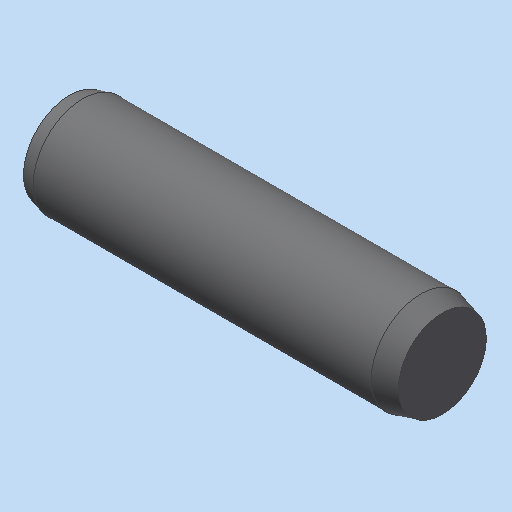
# Autodesk Inventor part: Zylinderstift_DIN_7979C_12_x_45
Saved by Autodesk Inventor 2023.3 (Build 273359000, 359)
## iProperties
Shininess: 64.0
Length Units: 11269
Angle Units: 11279
Time Units: 11290
Mass Units: 11283
Length Display Precision: 3
Angle Display Precision: 2
Compacted: True
Part Number: Zylinderstift_DIN_7979C_12_x_45
Document SubType Name: Modeling
Created: 2004-04-23
Description: =<RBPARTNOTITLE2>
Vendor: NORM8
Designer: C.Fischer
Manufacturer: Standard
Standards Organization: Custom
Density: 7.85 g/cm^3
Material: xStahl_AnP_Dummymaterial
Appearance: Stahl - normal AnP
Mass: 36.9517 g
Surface Area: 21.2882 cm^2
Volume: 4.70722 cm^3
Density: 0.0
Volumn: 0.0
Area: 0.0
PropertySet Name: Model Information
Control State: 0
Master: False
Checked Out: False
CNS_NB: Zylinderstift DIN 7979C 12 x 45
CNS_NN: DIN 7979-C
CNS_NT: Zylinderstift, mit Innengewinde, ungehaertet
CNS_NBSYN: Zylinderstift DIN 7979C $NENN.
CNS_LINA: Zylinderstift DIN 7979C 12 x 45
CNS_NENN: 12 x 45
CNS_D: 12.000
CNS_D1: 6.000
CNS_D2: 4.917
CNS_DA: 6.400
CNS_P: 1.000
CNS_L: 45.000
CNS_B: 10.000
CNS_T1: 1.200
CNS_T2: 16.000
CNS_A1: 2.600
CNS_A2: 1.600
CNS_KT: X
PSOL_IDENT_0: {C:\partsolutions\data\23d-libs\bosch_bamberg\stifte\scherstifte\din_7979_c.prj},170 {M=Nenngewinde}
PSOL_IDENT_1: ,{VTYP=3D},{NB=Zylinderstift DIN 7979C 12 x 45},{NN=DIN 7979-C},{DATE=26.11.2003},{GEOMDATE=26.11.20
PSOL_IDENT_2: 03},{VERSION=v1},{LINEID=410},{LINESUBID=-1},{WBVAR=}  {NB=Zylinderstift DIN 7979C 12 x 45},{LINA=Zy
PSOL_IDENT_3: linderstift DIN 7979C 12 x 45},{KT=X},{IDNR=},{NENN=12 x 45},{D=12.000},{D1=6.000},{D2=4.917},{DA=6.
PSOL_IDENT_4: 400},{P=1.000},{L=45.000},{B=10.000},{T1=1.200},{T2=16.000},{A1=2.600},{A2=1.600}
RBDRAWINGMISSINGSPEC: --
RBPARTNOTITLE2: Zylinderstift mit Innengewinde, ungehaertet
RBPARTNOTITLE1: Parallel pins with internal thread, unhardened
AnP_Kategorie: 5
RBPARTMADEOF: DIN 7979 C - 12 x 45
Title: Zylinderstift DIN 7979C 12 x 45
Author: C.Fischer
Keywords: =<RBPARTMADEOF>
Comments: =<RBSURFACE2>
Revision Number: 01
Autodesk Inventor part; units mm, degrees
sketch "Skizze_4" plane through (0, 0, 0) normal (0, 1, 0) x (-1, 0, 0)
  line L0 (-45, 0) -> (0, 0)
  line L1 (-17.4194, 0) -> (-16, -2.4585)
  line L2 (-16, -2.4585) -> (-2.4843, -2.4585)
  line L3 (-2.4843, -2.4585) -> (-1.2, -3.2)
  line L4 (-1.2, -3.2) -> (0, -3.2)
  line L5 (0, -3.2) -> (0, -5.5713)
  line L6 (0, -5.5713) -> (-1.6, -6)
  line L7 (-1.6, -6) -> (-42.4, -6)
  line L8 (-42.4, -6) -> (-45, -5.3033)
  line L9 (-45, -5.3033) -> (-45, 0)
  line L10 (-45, 0) -> (-17.4194, 0)
  constraints: 22 end point
revolve "Revolution1" add sketch "Skizze_4" angle 360 about axis through (45, 0, 0) along (1, 0, 0)
thread "Thread1" size "M6x1" class "6H" standard "ANSI Metric M Profile" length 13.5157
ref_plane "IP2_XY" through (0, 0, 0) normal (1, 0, 0) x (0, 0, -1)
ref_plane "IP2_YZ" through (0, 0, 0) normal (0, 0, -1) x (0, 1, 0)
ref_plane "IP1_XY" through (22.5, 0, 0) normal (1, 0, 0) x (0, 0, -1)
ref_plane "IP1_YZ" through (22.5, 0, 0) normal (0, 0, -1) x (0, 1, 0)
ref_plane "IP3_XY" through (45, 0, 0) normal (1, 0, 0) x (0, 0, -1)
ref_plane "IP3_YZ" through (45, 0, 0) normal (0, 0, -1) x (0, 1, 0)
